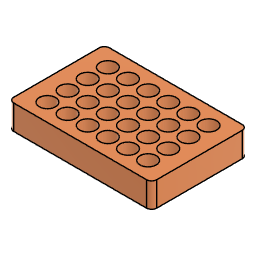
HyHAT_Mk1_Chassis (Autodesk Fusion 360 archive; units mm, degrees)
design "24 Well Plate"
Autodesk Fusion 360 part; units mm, degrees
sketch "Sketch3" plane through (0, 0, 0) normal (0, 0, 1) x (1, 0, 0)
  line L0 (0, 0) -> (-36, 0)
  line L1 (-36, 0) -> (-36, -18)
  line L2 (-36, -18) -> (0, -18)
  line L3 (0, -18) -> (0, 0)
  circle A0 centre (-36, -18) radius 7.25
  circle A1 centre (-18, -18) radius 7.25
  circle A2 centre (0, -18) radius 7.25
  circle A3 centre (18, -18) radius 7.25
  circle A4 centre (36, -18) radius 7.25
  circle A5 centre (54, -18) radius 7.25
  circle A6 centre (-36, 0) radius 7.25
  circle A7 centre (-18, 0) radius 7.25
  circle A8 centre (0, 0) radius 7.25
  circle A9 centre (18, 0) radius 7.25
  circle A10 centre (36, 0) radius 7.25
  circle A11 centre (54, 0) radius 7.25
  circle A12 centre (-36, 18) radius 7.25
  circle A13 centre (-18, 18) radius 7.25
  circle A14 centre (0, 18) radius 7.25
  circle A15 centre (18, 18) radius 7.25
  circle A16 centre (36, 18) radius 7.25
  circle A17 centre (54, 18) radius 7.25
  circle A18 centre (-36, 36) radius 7.25
  circle A19 centre (-18, 36) radius 7.25
  circle A20 centre (0, 36) radius 7.25
  circle A21 centre (18, 36) radius 7.25
  circle A22 centre (36, 36) radius 7.25
  circle A23 centre (54, 36) radius 7.25
  line L4 (-36, -18) -> (-54.88, -18)
  line L5 (-54.88, -18) -> (-54.88, -29.24)
  line L6 (-50.38, -33.74) -> (-36, -33.74)
  line L7 (-36, -33.74) -> (-36, -18)
  line L8 (-50.38, -33.74) -> (68.38, -33.74)
  line L9 (72.88, -29.24) -> (72.88, 47.24)
  line L10 (68.38, 51.74) -> (-50.38, 51.74)
  line L11 (-54.88, 47.24) -> (-54.88, -29.24)
  arc A24 (-50.38, 51.74) -> (-54.88, 47.24) centre (-50.38, 47.24) ccw
  arc A25 (72.88, 47.24) -> (68.38, 51.74) centre (68.38, 47.24) ccw
  arc A26 (68.38, -33.74) -> (72.88, -29.24) centre (68.38, -29.24) ccw
  arc A27 (-54.88, -29.24) -> (-50.38, -33.74) centre (-50.38, -29.24) ccw
  arc A28 (-54.88, -29.24) -> (-50.38, -33.74) centre (-50.38, -29.24) ccw
  point P0 (-54.88, -33.74)
  point P1 (72.88, -33.74)
  point P2 (-54.88, 51.74)
  dimension "d17" = 36
  dimension "d18" = 18
  dimension "d19" = 14.5
  dimension "d22" = 18
  dimension "d23" = 18
  dimension "d24" = 18.88
  dimension "d25" = 15.74
  dimension "d26" = 127.76
  dimension "d27" = 85.48
  dimension "d28" = 4.5
  constraint horizontal L0
  constraint vertical L1
  constraint horizontal L2
  constraint vertical L3
  constraint coincident L0.start L3.end
  constraint coincident L1.end L2.start
  constraint horizontal L4
  constraint vertical L5
  constraint horizontal L6
  constraint vertical L7
  constraint horizontal L8
  constraint vertical L9
  constraint horizontal L10
  constraint vertical L11
  constraint coincident P2 L10
  constraint coincident P2 L11
  constraint tangent L10 A24
  constraint tangent L11 A24
  constraint tangent L10 A25
  constraint tangent L9 A25
  constraint equal A24 A25
  constraint coincident P1 L9
  constraint coincident P1 L8
  constraint tangent L9 A26
  constraint tangent L8 A26
  constraint equal A24 A26
  constraint coincident P0 L8
  constraint coincident P0 L11
  constraint tangent L8 A27
  constraint tangent L11 A27
  constraint equal A24 A27
  constraint coincident P0 L6
  constraint coincident P0 L5
  constraint tangent L6 A28
  constraint tangent L5 A28
  constraint equal A24 A28
  measures "d17" distance of L0.start L0.end
  measures "d18" distance of L0.start L2.end
  measures "d19" diameter of A0
  measures "d24" distance of L1.end L4.end
  measures "d25" distance of L1.end L6.end
  measures "d26" distance of P0 P1
  measures "d27" distance of P0 P2
  measures "d28" radius of A24
extrude "Extrude2" add sketch "Sketch3" along normal blind 22 contours L0 L1 L2 L3 A0 A1 A2 A6 A7 A8 L4 L7 L8 L9 L10 L11 A24 A25 A26 | L0 L1 L2 L3 A0 A1 A2 A6 A7 A8 | A0 L4 L5 L6 L7 L8 L11 A27 A28
equation "d17 = ( 18 * 2 ) * 1 mm"
